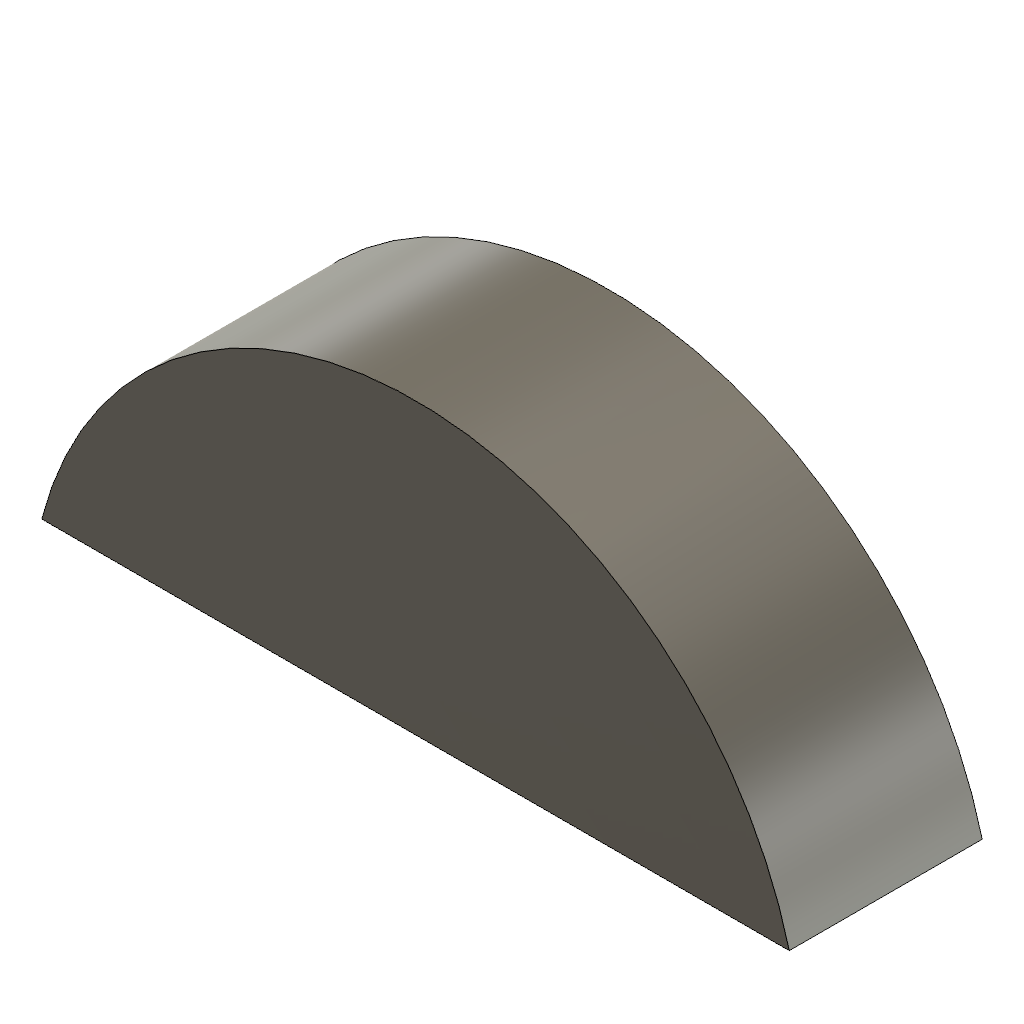
line_circle_reverse_creation (Autodesk Fusion 360 design; units mm, degrees)
part number: 2026-10-21-12-11-53-660
Autodesk Fusion 360 part; units mm, degrees
sketch "TrimmedProfileSources" plane through (0, 0, 0) normal (0, 0, 1) x (1, 0, 0)
  line L0 (-30, 5) -> (30, 5)
  circle A0 centre (0, 0) radius 20
extrude "SelectedTrimmedProfile" add sketch "TrimmedProfileSources" along normal blind 10 contours L0 A0 picked at (-2.2145, 15.0125)
